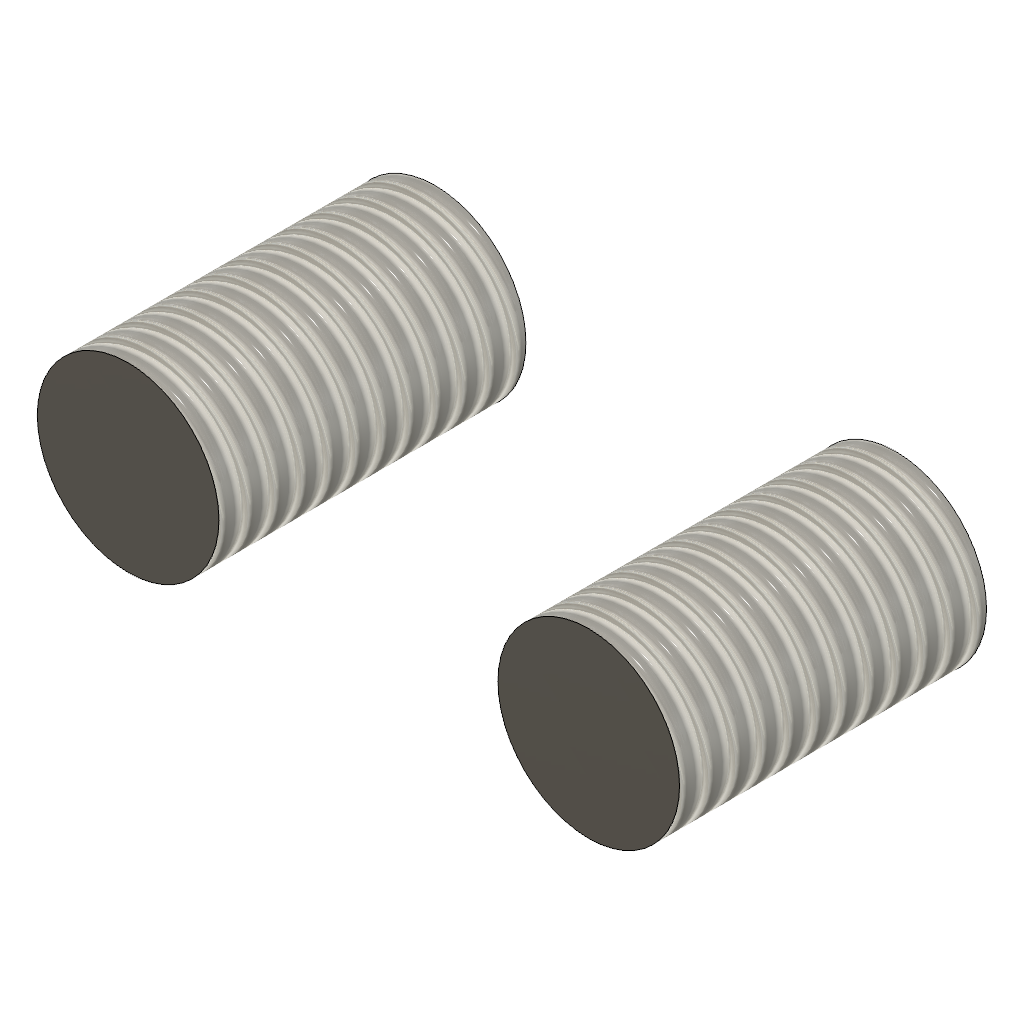
external_two_full (Autodesk Fusion 360 design; units mm, degrees)
part number: 2026-10-21-15-54-50-286
Autodesk Fusion 360 part; units mm, degrees
sketch "OwnedThreadProfile_0_external_two_full" plane through (0, 0, 0) normal (0, 0, 1) x (1, 0, 0)
  circle A0 centre (0, 0) radius 6
extrude "OwnedThreadCylinderExtrude_0_external_two_full" add sketch "OwnedThreadProfile_0_external_two_full" along normal blind 20 makes body 1
sketch "OwnedThreadProfile_1_external_two_full" plane through (0, 0, 0) normal (0, 0, 1) x (1, 0, 0)
  circle A0 centre (30, 0) radius 6
extrude "OwnedThreadCylinderExtrude_1_external_two_full" add sketch "OwnedThreadProfile_1_external_two_full" along normal blind 20 separate body makes body 2
thread "OwnedThreadMultiFace_external_two_full" "ISO Metric profile 12.0 M12x1.75 M12x1.75 6g" major diameter 11.8335 minor diameter 9.8365 pitch 1.75 angle 60 resizes the face on face at (35.9925, -0.2991, 13.3333) on face at (5.9925, -0.2991, 13.3333) on bodies 1 2
named bodies: "OwnedThreadCylinder_0_external_two_full", "OwnedThreadCylinder_1_external_two_full"
